Autodesk Fusion 360 part; units mm, degrees
(part 5 of 7)
equation "d301 = -( wall + 0.2 mm )"
equation "d303 = abs(( 1 ) * ( ( ( 1 ) * jointNodeQ * sqrt(2) - bodyWidth / 2 * cos(315 deg) + ( ( 1 ) * nodeHalfWidth ) * sin(315 deg) ) + ( 0 ) * ( ( 1 ) * endNodeX - ( ( 1 ) * jointNodeQ * sqrt(2) - bodyWidth / 2 * cos(315 deg) + ( ( 1 ) * nodeHalfWidth ) * sin(315 deg) ) ) ) + ( 0 ) * ( ( 1 ) * nodeHalfWidth ))"
equation "d304 = abs(( 0 ) * ( ( ( 1 ) * jointNodeQ * sqrt(2) - bodyWidth / 2 * cos(315 deg) + ( ( 1 ) * nodeHalfWidth ) * sin(315 deg) ) + ( 0 ) * ( ( 1 ) * endNodeX - ( ( 1 ) * jointNodeQ * sqrt(2) - bodyWidth / 2 * cos(315 deg) + ( ( 1 ) * nodeHalfWidth ) * sin(315 deg) ) ) ) + ( -1 ) * ( ( 1 ) * nodeHalfWidth ))"
equation "d305 = abs(( 1 ) * ( ( ( 1 ) * jointNodeQ * sqrt(2) - bodyWidth / 2 * cos(315 deg) + ( ( -1 ) * nodeHalfWidth ) * sin(315 deg) ) + ( 0.333333333333333 ) * ( ( 1 ) * endNodeX - ( ( 1 ) * jointNodeQ * sqrt(2) - bodyWidth / 2 * cos(315 deg) + ( ( -1 ) * nodeHalfWidth ) * sin(315 deg) ) ) ) + ( 0 ) * ( ( -1 ) * nodeHalfWidth ))"
equation "d306 = abs(( 0 ) * ( ( ( 1 ) * jointNodeQ * sqrt(2) - bodyWidth / 2 * cos(315 deg) + ( ( -1 ) * nodeHalfWidth ) * sin(315 deg) ) + ( 0.333333333333333 ) * ( ( 1 ) * endNodeX - ( ( 1 ) * jointNodeQ * sqrt(2) - bodyWidth / 2 * cos(315 deg) + ( ( -1 ) * nodeHalfWidth ) * sin(315 deg) ) ) ) + ( -1 ) * ( ( -1 ) * nodeHalfWidth ))"
equation "d307 = abs(( 1 ) * ( ( ( 1 ) * jointNodeQ * sqrt(2) - bodyWidth / 2 * cos(315 deg) + ( ( 1 ) * nodeHalfWidth ) * sin(315 deg) ) + ( 0.666666666666667 ) * ( ( 1 ) * endNodeX - ( ( 1 ) * jointNodeQ * sqrt(2) - bodyWidth / 2 * cos(315 deg) + ( ( 1 ) * nodeHalfWidth ) * sin(315 deg) ) ) ) + ( 0 ) * ( ( 1 ) * nodeHalfWidth ))"
equation "d308 = abs(( 0 ) * ( ( ( 1 ) * jointNodeQ * sqrt(2) - bodyWidth / 2 * cos(315 deg) + ( ( 1 ) * nodeHalfWidth ) * sin(315 deg) ) + ( 0.666666666666667 ) * ( ( 1 ) * endNodeX - ( ( 1 ) * jointNodeQ * sqrt(2) - bodyWidth / 2 * cos(315 deg) + ( ( 1 ) * nodeHalfWidth ) * sin(315 deg) ) ) ) + ( -1 ) * ( ( 1 ) * nodeHalfWidth ))"
equation "d309 = memberWidth / 2"
equation "d310 = -( wall + 0.2 mm )"
equation "d312 = abs(( 1 ) * ( ( ( 1 ) * jointNodeQ * sqrt(2) - bodyWidth / 2 * cos(315 deg) + ( ( -1 ) * nodeHalfWidth ) * sin(315 deg) ) + ( 0.333333333333333 ) * ( ( 1 ) * endNodeX - ( ( 1 ) * jointNodeQ * sqrt(2) - bodyWidth / 2 * cos(315 deg) + ( ( -1 ) * nodeHalfWidth ) * sin(315 deg) ) ) ) + ( 0 ) * ( ( -1 ) * nodeHalfWidth ))"
equation "d313 = abs(( 0 ) * ( ( ( 1 ) * jointNodeQ * sqrt(2) - bodyWidth / 2 * cos(315 deg) + ( ( -1 ) * nodeHalfWidth ) * sin(315 deg) ) + ( 0.333333333333333 ) * ( ( 1 ) * endNodeX - ( ( 1 ) * jointNodeQ * sqrt(2) - bodyWidth / 2 * cos(315 deg) + ( ( -1 ) * nodeHalfWidth ) * sin(315 deg) ) ) ) + ( -1 ) * ( ( -1 ) * nodeHalfWidth ))"
equation "d314 = abs(( 1 ) * ( ( ( 1 ) * jointNodeQ * sqrt(2) - bodyWidth / 2 * cos(315 deg) + ( ( 1 ) * nodeHalfWidth ) * sin(315 deg) ) + ( 0.666666666666667 ) * ( ( 1 ) * endNodeX - ( ( 1 ) * jointNodeQ * sqrt(2) - bodyWidth / 2 * cos(315 deg) + ( ( 1 ) * nodeHalfWidth ) * sin(315 deg) ) ) ) + ( 0 ) * ( ( 1 ) * nodeHalfWidth ))"
equation "d315 = abs(( 0 ) * ( ( ( 1 ) * jointNodeQ * sqrt(2) - bodyWidth / 2 * cos(315 deg) + ( ( 1 ) * nodeHalfWidth ) * sin(315 deg) ) + ( 0.666666666666667 ) * ( ( 1 ) * endNodeX - ( ( 1 ) * jointNodeQ * sqrt(2) - bodyWidth / 2 * cos(315 deg) + ( ( 1 ) * nodeHalfWidth ) * sin(315 deg) ) ) ) + ( -1 ) * ( ( 1 ) * nodeHalfWidth ))"
equation "d316 = abs(( 1 ) * ( ( ( 1 ) * jointNodeQ * sqrt(2) - bodyWidth / 2 * cos(315 deg) + ( ( -1 ) * nodeHalfWidth ) * sin(315 deg) ) + ( 1 ) * ( ( 1 ) * endNodeX - ( ( 1 ) * jointNodeQ * sqrt(2) - bodyWidth / 2 * cos(315 deg) + ( ( -1 ) * nodeHalfWidth ) * sin(315 deg) ) ) ) + ( 0 ) * ( ( -1 ) * nodeHalfWidth ))"
equation "d317 = abs(( 0 ) * ( ( ( 1 ) * jointNodeQ * sqrt(2) - bodyWidth / 2 * cos(315 deg) + ( ( -1 ) * nodeHalfWidth ) * sin(315 deg) ) + ( 1 ) * ( ( 1 ) * endNodeX - ( ( 1 ) * jointNodeQ * sqrt(2) - bodyWidth / 2 * cos(315 deg) + ( ( -1 ) * nodeHalfWidth ) * sin(315 deg) ) ) ) + ( -1 ) * ( ( -1 ) * nodeHalfWidth ))"
equation "d318 = -memberWidth / 2"
equation "d319 = -( wall + 0.2 mm )"
equation "d321 = abs(( 1 ) * ( ( ( 1 ) * jointNodeQ * sqrt(2) - bodyWidth / 2 * cos(315 deg) + ( ( 1 ) * nodeHalfWidth ) * sin(315 deg) ) + ( 0.666666666666667 ) * ( ( 1 ) * endNodeX - ( ( 1 ) * jointNodeQ * sqrt(2) - bodyWidth / 2 * cos(315 deg) + ( ( 1 ) * nodeHalfWidth ) * sin(315 deg) ) ) ) + ( 0 ) * ( ( 1 ) * nodeHalfWidth ))"
equation "d322 = abs(( 0 ) * ( ( ( 1 ) * jointNodeQ * sqrt(2) - bodyWidth / 2 * cos(315 deg) + ( ( 1 ) * nodeHalfWidth ) * sin(315 deg) ) + ( 0.666666666666667 ) * ( ( 1 ) * endNodeX - ( ( 1 ) * jointNodeQ * sqrt(2) - bodyWidth / 2 * cos(315 deg) + ( ( 1 ) * nodeHalfWidth ) * sin(315 deg) ) ) ) + ( -1 ) * ( ( 1 ) * nodeHalfWidth ))"
equation "d323 = abs(( 1 ) * ( ( ( 1 ) * jointNodeQ * sqrt(2) - bodyWidth / 2 * cos(315 deg) + ( ( -1 ) * nodeHalfWidth ) * sin(315 deg) ) + ( 1 ) * ( ( 1 ) * endNodeX - ( ( 1 ) * jointNodeQ * sqrt(2) - bodyWidth / 2 * cos(315 deg) + ( ( -1 ) * nodeHalfWidth ) * sin(315 deg) ) ) ) + ( 0 ) * ( ( -1 ) * nodeHalfWidth ))"
equation "d324 = abs(( 0 ) * ( ( ( 1 ) * jointNodeQ * sqrt(2) - bodyWidth / 2 * cos(315 deg) + ( ( -1 ) * nodeHalfWidth ) * sin(315 deg) ) + ( 1 ) * ( ( 1 ) * endNodeX - ( ( 1 ) * jointNodeQ * sqrt(2) - bodyWidth / 2 * cos(315 deg) + ( ( -1 ) * nodeHalfWidth ) * sin(315 deg) ) ) ) + ( -1 ) * ( ( -1 ) * nodeHalfWidth ))"
equation "d325 = abs(( 1 ) * ( ( ( 1 ) * jointNodeQ * sqrt(2) - bodyWidth / 2 * cos(315 deg) + ( ( 1 ) * nodeHalfWidth ) * sin(315 deg) ) + ( 1 ) * ( ( 1 ) * endNodeX - ( ( 1 ) * jointNodeQ * sqrt(2) - bodyWidth / 2 * cos(315 deg) + ( ( 1 ) * nodeHalfWidth ) * sin(315 deg) ) ) ) + ( 0 ) * ( ( 1 ) * nodeHalfWidth ))"
equation "d326 = abs(( 0 ) * ( ( ( 1 ) * jointNodeQ * sqrt(2) - bodyWidth / 2 * cos(315 deg) + ( ( 1 ) * nodeHalfWidth ) * sin(315 deg) ) + ( 1 ) * ( ( 1 ) * endNodeX - ( ( 1 ) * jointNodeQ * sqrt(2) - bodyWidth / 2 * cos(315 deg) + ( ( 1 ) * nodeHalfWidth ) * sin(315 deg) ) ) ) + ( -1 ) * ( ( 1 ) * nodeHalfWidth ))"
equation "d327 = memberWidth / 2"
equation "d328 = -( wall + 0.2 mm )"
equation "d331 = apertureRadius"
equation "d334 = bodyWidth / 2"
equation "d336 = abs(( 1 ) * ( ( ( -1 ) * jointNodeQ * sqrt(2) - bodyWidth / 2 * cos(0 deg) + ( ( -1 ) * nodeHalfWidth ) * sin(0 deg) ) + ( 0 ) * ( ( -1 ) * endNodeX - ( ( -1 ) * jointNodeQ * sqrt(2) - bodyWidth / 2 * cos(0 deg) + ( ( -1 ) * nodeHalfWidth ) * sin(0 deg) ) ) ) + ( 0 ) * ( ( -1 ) * nodeHalfWidth ))"
equation "d337 = abs(( 0 ) * ( ( ( -1 ) * jointNodeQ * sqrt(2) - bodyWidth / 2 * cos(0 deg) + ( ( -1 ) * nodeHalfWidth ) * sin(0 deg) ) + ( 0 ) * ( ( -1 ) * endNodeX - ( ( -1 ) * jointNodeQ * sqrt(2) - bodyWidth / 2 * cos(0 deg) + ( ( -1 ) * nodeHalfWidth ) * sin(0 deg) ) ) ) + ( -1 ) * ( ( -1 ) * nodeHalfWidth ))"
equation "d338 = abs(( 1 ) * ( ( ( -1 ) * jointNodeQ * sqrt(2) - bodyWidth / 2 * cos(0 deg) + ( ( 1 ) * nodeHalfWidth ) * sin(0 deg) ) + ( 0 ) * ( ( -1 ) * endNodeX - ( ( -1 ) * jointNodeQ * sqrt(2) - bodyWidth / 2 * cos(0 deg) + ( ( 1 ) * nodeHalfWidth ) * sin(0 deg) ) ) ) + ( 0 ) * ( ( 1 ) * nodeHalfWidth ))"
equation "d339 = abs(( 0 ) * ( ( ( -1 ) * jointNodeQ * sqrt(2) - bodyWidth / 2 * cos(0 deg) + ( ( 1 ) * nodeHalfWidth ) * sin(0 deg) ) + ( 0 ) * ( ( -1 ) * endNodeX - ( ( -1 ) * jointNodeQ * sqrt(2) - bodyWidth / 2 * cos(0 deg) + ( ( 1 ) * nodeHalfWidth ) * sin(0 deg) ) ) ) + ( -1 ) * ( ( 1 ) * nodeHalfWidth ))"
equation "d340 = abs(( 1 ) * ( ( ( -1 ) * jointNodeQ * sqrt(2) - bodyWidth / 2 * cos(0 deg) + ( ( -1 ) * nodeHalfWidth ) * sin(0 deg) ) + ( 1 ) * ( ( -1 ) * endNodeX - ( ( -1 ) * jointNodeQ * sqrt(2) - bodyWidth / 2 * cos(0 deg) + ( ( -1 ) * nodeHalfWidth ) * sin(0 deg) ) ) ) + ( 0 ) * ( ( -1 ) * nodeHalfWidth ))"
equation "d341 = abs(( 0 ) * ( ( ( -1 ) * jointNodeQ * sqrt(2) - bodyWidth / 2 * cos(0 deg) + ( ( -1 ) * nodeHalfWidth ) * sin(0 deg) ) + ( 1 ) * ( ( -1 ) * endNodeX - ( ( -1 ) * jointNodeQ * sqrt(2) - bodyWidth / 2 * cos(0 deg) + ( ( -1 ) * nodeHalfWidth ) * sin(0 deg) ) ) ) + ( -1 ) * ( ( -1 ) * nodeHalfWidth ))"
equation "d342 = memberWidth / 2"
equation "d343 = -( wall + 0.2 mm )"
equation "d345 = abs(( 1 ) * ( ( ( -1 ) * jointNodeQ * sqrt(2) - bodyWidth / 2 * cos(0 deg) + ( ( 1 ) * nodeHalfWidth ) * sin(0 deg) ) + ( 0 ) * ( ( -1 ) * endNodeX - ( ( -1 ) * jointNodeQ * sqrt(2) - bodyWidth / 2 * cos(0 deg) + ( ( 1 ) * nodeHalfWidth ) * sin(0 deg) ) ) ) + ( 0 ) * ( ( 1 ) * nodeHalfWidth ))"
equation "d346 = abs(( 0 ) * ( ( ( -1 ) * jointNodeQ * sqrt(2) - bodyWidth / 2 * cos(0 deg) + ( ( 1 ) * nodeHalfWidth ) * sin(0 deg) ) + ( 0 ) * ( ( -1 ) * endNodeX - ( ( -1 ) * jointNodeQ * sqrt(2) - bodyWidth / 2 * cos(0 deg) + ( ( 1 ) * nodeHalfWidth ) * sin(0 deg) ) ) ) + ( -1 ) * ( ( 1 ) * nodeHalfWidth ))"
equation "d347 = abs(( 1 ) * ( ( ( -1 ) * jointNodeQ * sqrt(2) - bodyWidth / 2 * cos(0 deg) + ( ( -1 ) * nodeHalfWidth ) * sin(0 deg) ) + ( 1 ) * ( ( -1 ) * endNodeX - ( ( -1 ) * jointNodeQ * sqrt(2) - bodyWidth / 2 * cos(0 deg) + ( ( -1 ) * nodeHalfWidth ) * sin(0 deg) ) ) ) + ( 0 ) * ( ( -1 ) * nodeHalfWidth ))"
equation "d348 = abs(( 0 ) * ( ( ( -1 ) * jointNodeQ * sqrt(2) - bodyWidth / 2 * cos(0 deg) + ( ( -1 ) * nodeHalfWidth ) * sin(0 deg) ) + ( 1 ) * ( ( -1 ) * endNodeX - ( ( -1 ) * jointNodeQ * sqrt(2) - bodyWidth / 2 * cos(0 deg) + ( ( -1 ) * nodeHalfWidth ) * sin(0 deg) ) ) ) + ( -1 ) * ( ( -1 ) * nodeHalfWidth ))"
equation "d349 = abs(( 1 ) * ( ( ( -1 ) * jointNodeQ * sqrt(2) - bodyWidth / 2 * cos(0 deg) + ( ( 1 ) * nodeHalfWidth ) * sin(0 deg) ) + ( 1 ) * ( ( -1 ) * endNodeX - ( ( -1 ) * jointNodeQ * sqrt(2) - bodyWidth / 2 * cos(0 deg) + ( ( 1 ) * nodeHalfWidth ) * sin(0 deg) ) ) ) + ( 0 ) * ( ( 1 ) * nodeHalfWidth ))"
equation "d350 = abs(( 0 ) * ( ( ( -1 ) * jointNodeQ * sqrt(2) - bodyWidth / 2 * cos(0 deg) + ( ( 1 ) * nodeHalfWidth ) * sin(0 deg) ) + ( 1 ) * ( ( -1 ) * endNodeX - ( ( -1 ) * jointNodeQ * sqrt(2) - bodyWidth / 2 * cos(0 deg) + ( ( 1 ) * nodeHalfWidth ) * sin(0 deg) ) ) ) + ( -1 ) * ( ( 1 ) * nodeHalfWidth ))"
equation "d351 = -memberWidth / 2"
equation "d352 = -( wall + 0.2 mm )"
equation "d355 = apertureRadius"
equation "d358 = bodyWidth / 2"
equation "d360 = abs(( 1 ) * ( ( ( -1 ) * jointNodeQ * sqrt(2) - bodyWidth / 2 * cos(45 deg) + ( ( -1 ) * nodeHalfWidth ) * sin(45 deg) ) + ( 0 ) * ( ( -1 ) * endNodeX - ( ( -1 ) * jointNodeQ * sqrt(2) - bodyWidth / 2 * cos(45 deg) + ( ( -1 ) * nodeHalfWidth ) * sin(45 deg) ) ) ) + ( 0 ) * ( ( -1 ) * nodeHalfWidth ))"
equation "d361 = abs(( 0 ) * ( ( ( -1 ) * jointNodeQ * sqrt(2) - bodyWidth / 2 * cos(45 deg) + ( ( -1 ) * nodeHalfWidth ) * sin(45 deg) ) + ( 0 ) * ( ( -1 ) * endNodeX - ( ( -1 ) * jointNodeQ * sqrt(2) - bodyWidth / 2 * cos(45 deg) + ( ( -1 ) * nodeHalfWidth ) * sin(45 deg) ) ) ) + ( -1 ) * ( ( -1 ) * nodeHalfWidth ))"
equation "d362 = abs(( 1 ) * ( ( ( -1 ) * jointNodeQ * sqrt(2) - bodyWidth / 2 * cos(45 deg) + ( ( 1 ) * nodeHalfWidth ) * sin(45 deg) ) + ( 0 ) * ( ( -1 ) * endNodeX - ( ( -1 ) * jointNodeQ * sqrt(2) - bodyWidth / 2 * cos(45 deg) + ( ( 1 ) * nodeHalfWidth ) * sin(45 deg) ) ) ) + ( 0 ) * ( ( 1 ) * nodeHalfWidth ))"
equation "d363 = abs(( 0 ) * ( ( ( -1 ) * jointNodeQ * sqrt(2) - bodyWidth / 2 * cos(45 deg) + ( ( 1 ) * nodeHalfWidth ) * sin(45 deg) ) + ( 0 ) * ( ( -1 ) * endNodeX - ( ( -1 ) * jointNodeQ * sqrt(2) - bodyWidth / 2 * cos(45 deg) + ( ( 1 ) * nodeHalfWidth ) * sin(45 deg) ) ) ) + ( -1 ) * ( ( 1 ) * nodeHalfWidth ))"
equation "d364 = abs(( 1 ) * ( ( ( -1 ) * jointNodeQ * sqrt(2) - bodyWidth / 2 * cos(45 deg) + ( ( -1 ) * nodeHalfWidth ) * sin(45 deg) ) + ( 1 ) * ( ( -1 ) * endNodeX - ( ( -1 ) * jointNodeQ * sqrt(2) - bodyWidth / 2 * cos(45 deg) + ( ( -1 ) * nodeHalfWidth ) * sin(45 deg) ) ) ) + ( 0 ) * ( ( -1 ) * nodeHalfWidth ))"
equation "d365 = abs(( 0 ) * ( ( ( -1 ) * jointNodeQ * sqrt(2) - bodyWidth / 2 * cos(45 deg) + ( ( -1 ) * nodeHalfWidth ) * sin(45 deg) ) + ( 1 ) * ( ( -1 ) * endNodeX - ( ( -1 ) * jointNodeQ * sqrt(2) - bodyWidth / 2 * cos(45 deg) + ( ( -1 ) * nodeHalfWidth ) * sin(45 deg) ) ) ) + ( -1 ) * ( ( -1 ) * nodeHalfWidth ))"
equation "d366 = memberWidth / 2"
equation "d367 = -( wall + 0.2 mm )"
equation "d369 = abs(( 1 ) * ( ( ( -1 ) * jointNodeQ * sqrt(2) - bodyWidth / 2 * cos(45 deg) + ( ( 1 ) * nodeHalfWidth ) * sin(45 deg) ) + ( 0 ) * ( ( -1 ) * endNodeX - ( ( -1 ) * jointNodeQ * sqrt(2) - bodyWidth / 2 * cos(45 deg) + ( ( 1 ) * nodeHalfWidth ) * sin(45 deg) ) ) ) + ( 0 ) * ( ( 1 ) * nodeHalfWidth ))"
equation "d370 = abs(( 0 ) * ( ( ( -1 ) * jointNodeQ * sqrt(2) - bodyWidth / 2 * cos(45 deg) + ( ( 1 ) * nodeHalfWidth ) * sin(45 deg) ) + ( 0 ) * ( ( -1 ) * endNodeX - ( ( -1 ) * jointNodeQ * sqrt(2) - bodyWidth / 2 * cos(45 deg) + ( ( 1 ) * nodeHalfWidth ) * sin(45 deg) ) ) ) + ( -1 ) * ( ( 1 ) * nodeHalfWidth ))"
equation "d371 = abs(( 1 ) * ( ( ( -1 ) * jointNodeQ * sqrt(2) - bodyWidth / 2 * cos(45 deg) + ( ( -1 ) * nodeHalfWidth ) * sin(45 deg) ) + ( 1 ) * ( ( -1 ) * endNodeX - ( ( -1 ) * jointNodeQ * sqrt(2) - bodyWidth / 2 * cos(45 deg) + ( ( -1 ) * nodeHalfWidth ) * sin(45 deg) ) ) ) + ( 0 ) * ( ( -1 ) * nodeHalfWidth ))"
equation "d372 = abs(( 0 ) * ( ( ( -1 ) * jointNodeQ * sqrt(2) - bodyWidth / 2 * cos(45 deg) + ( ( -1 ) * nodeHalfWidth ) * sin(45 deg) ) + ( 1 ) * ( ( -1 ) * endNodeX - ( ( -1 ) * jointNodeQ * sqrt(2) - bodyWidth / 2 * cos(45 deg) + ( ( -1 ) * nodeHalfWidth ) * sin(45 deg) ) ) ) + ( -1 ) * ( ( -1 ) * nodeHalfWidth ))"
equation "d373 = abs(( 1 ) * ( ( ( -1 ) * jointNodeQ * sqrt(2) - bodyWidth / 2 * cos(45 deg) + ( ( 1 ) * nodeHalfWidth ) * sin(45 deg) ) + ( 1 ) * ( ( -1 ) * endNodeX - ( ( -1 ) * jointNodeQ * sqrt(2) - bodyWidth / 2 * cos(45 deg) + ( ( 1 ) * nodeHalfWidth ) * sin(45 deg) ) ) ) + ( 0 ) * ( ( 1 ) * nodeHalfWidth ))"
equation "d374 = abs(( 0 ) * ( ( ( -1 ) * jointNodeQ * sqrt(2) - bodyWidth / 2 * cos(45 deg) + ( ( 1 ) * nodeHalfWidth ) * sin(45 deg) ) + ( 1 ) * ( ( -1 ) * endNodeX - ( ( -1 ) * jointNodeQ * sqrt(2) - bodyWidth / 2 * cos(45 deg) + ( ( 1 ) * nodeHalfWidth ) * sin(45 deg) ) ) ) + ( -1 ) * ( ( 1 ) * nodeHalfWidth ))"
equation "d375 = -memberWidth / 2"
equation "d376 = -( wall + 0.2 mm )"
equation "d379 = apertureRadius"
equation "d382 = bodyWidth / 2"
equation "d384 = abs(( 1 ) * ( ( ( -1 ) * jointNodeQ * sqrt(2) - bodyWidth / 2 * cos(90 deg) + ( ( 1 ) * nodeHalfWidth ) * sin(90 deg) ) + ( 0 ) * ( ( -1 ) * endNodeX - ( ( -1 ) * jointNodeQ * sqrt(2) - bodyWidth / 2 * cos(90 deg) + ( ( 1 ) * nodeHalfWidth ) * sin(90 deg) ) ) ) + ( 0 ) * ( ( 1 ) * nodeHalfWidth ))"
equation "d385 = abs(( 0 ) * ( ( ( -1 ) * jointNodeQ * sqrt(2) - bodyWidth / 2 * cos(90 deg) + ( ( 1 ) * nodeHalfWidth ) * sin(90 deg) ) + ( 0 ) * ( ( -1 ) * endNodeX - ( ( -1 ) * jointNodeQ * sqrt(2) - bodyWidth / 2 * cos(90 deg) + ( ( 1 ) * nodeHalfWidth ) * sin(90 deg) ) ) ) + ( -1 ) * ( ( 1 ) * nodeHalfWidth ))"
equation "d386 = abs(( 1 ) * ( ( ( -1 ) * jointNodeQ * sqrt(2) - bodyWidth / 2 * cos(90 deg) + ( ( -1 ) * nodeHalfWidth ) * sin(90 deg) ) + ( 0 ) * ( ( -1 ) * endNodeX - ( ( -1 ) * jointNodeQ * sqrt(2) - bodyWidth / 2 * cos(90 deg) + ( ( -1 ) * nodeHalfWidth ) * sin(90 deg) ) ) ) + ( 0 ) * ( ( -1 ) * nodeHalfWidth ))"
equation "d387 = abs(( 0 ) * ( ( ( -1 ) * jointNodeQ * sqrt(2) - bodyWidth / 2 * cos(90 deg) + ( ( -1 ) * nodeHalfWidth ) * sin(90 deg) ) + ( 0 ) * ( ( -1 ) * endNodeX - ( ( -1 ) * jointNodeQ * sqrt(2) - bodyWidth / 2 * cos(90 deg) + ( ( -1 ) * nodeHalfWidth ) * sin(90 deg) ) ) ) + ( -1 ) * ( ( -1 ) * nodeHalfWidth ))"
equation "d388 = abs(( 1 ) * ( ( ( -1 ) * jointNodeQ * sqrt(2) - bodyWidth / 2 * cos(90 deg) + ( ( 1 ) * nodeHalfWidth ) * sin(90 deg) ) + ( 0.5 ) * ( ( -1 ) * endNodeX - ( ( -1 ) * jointNodeQ * sqrt(2) - bodyWidth / 2 * cos(90 deg) + ( ( 1 ) * nodeHalfWidth ) * sin(90 deg) ) ) ) + ( 0 ) * ( ( 1 ) * nodeHalfWidth ))"
equation "d389 = abs(( 0 ) * ( ( ( -1 ) * jointNodeQ * sqrt(2) - bodyWidth / 2 * cos(90 deg) + ( ( 1 ) * nodeHalfWidth ) * sin(90 deg) ) + ( 0.5 ) * ( ( -1 ) * endNodeX - ( ( -1 ) * jointNodeQ * sqrt(2) - bodyWidth / 2 * cos(90 deg) + ( ( 1 ) * nodeHalfWidth ) * sin(90 deg) ) ) ) + ( -1 ) * ( ( 1 ) * nodeHalfWidth ))"
equation "d390 = -memberWidth / 2"
equation "d391 = -( wall + 0.2 mm )"
equation "d393 = abs(( 1 ) * ( ( ( -1 ) * jointNodeQ * sqrt(2) - bodyWidth / 2 * cos(90 deg) + ( ( -1 ) * nodeHalfWidth ) * sin(90 deg) ) + ( 0 ) * ( ( -1 ) * endNodeX - ( ( -1 ) * jointNodeQ * sqrt(2) - bodyWidth / 2 * cos(90 deg) + ( ( -1 ) * nodeHalfWidth ) * sin(90 deg) ) ) ) + ( 0 ) * ( ( -1 ) * nodeHalfWidth ))"
equation "d394 = abs(( 0 ) * ( ( ( -1 ) * jointNodeQ * sqrt(2) - bodyWidth / 2 * cos(90 deg) + ( ( -1 ) * nodeHalfWidth ) * sin(90 deg) ) + ( 0 ) * ( ( -1 ) * endNodeX - ( ( -1 ) * jointNodeQ * sqrt(2) - bodyWidth / 2 * cos(90 deg) + ( ( -1 ) * nodeHalfWidth ) * sin(90 deg) ) ) ) + ( -1 ) * ( ( -1 ) * nodeHalfWidth ))"
equation "d395 = abs(( 1 ) * ( ( ( -1 ) * jointNodeQ * sqrt(2) - bodyWidth / 2 * cos(90 deg) + ( ( 1 ) * nodeHalfWidth ) * sin(90 deg) ) + ( 0.5 ) * ( ( -1 ) * endNodeX - ( ( -1 ) * jointNodeQ * sqrt(2) - bodyWidth / 2 * cos(90 deg) + ( ( 1 ) * nodeHalfWidth ) * sin(90 deg) ) ) ) + ( 0 ) * ( ( 1 ) * nodeHalfWidth ))"
equation "d396 = abs(( 0 ) * ( ( ( -1 ) * jointNodeQ * sqrt(2) - bodyWidth / 2 * cos(90 deg) + ( ( 1 ) * nodeHalfWidth ) * sin(90 deg) ) + ( 0.5 ) * ( ( -1 ) * endNodeX - ( ( -1 ) * jointNodeQ * sqrt(2) - bodyWidth / 2 * cos(90 deg) + ( ( 1 ) * nodeHalfWidth ) * sin(90 deg) ) ) ) + ( -1 ) * ( ( 1 ) * nodeHalfWidth ))"
equation "d397 = abs(( 1 ) * ( ( ( -1 ) * jointNodeQ * sqrt(2) - bodyWidth / 2 * cos(90 deg) + ( ( -1 ) * nodeHalfWidth ) * sin(90 deg) ) + ( 1 ) * ( ( -1 ) * endNodeX - ( ( -1 ) * jointNodeQ * sqrt(2) - bodyWidth / 2 * cos(90 deg) + ( ( -1 ) * nodeHalfWidth ) * sin(90 deg) ) ) ) + ( 0 ) * ( ( -1 ) * nodeHalfWidth ))"
equation "d398 = abs(( 0 ) * ( ( ( -1 ) * jointNodeQ * sqrt(2) - bodyWidth / 2 * cos(90 deg) + ( ( -1 ) * nodeHalfWidth ) * sin(90 deg) ) + ( 1 ) * ( ( -1 ) * endNodeX - ( ( -1 ) * jointNodeQ * sqrt(2) - bodyWidth / 2 * cos(90 deg) + ( ( -1 ) * nodeHalfWidth ) * sin(90 deg) ) ) ) + ( -1 ) * ( ( -1 ) * nodeHalfWidth ))"
equation "d399 = memberWidth / 2"
equation "d400 = -( wall + 0.2 mm )"
equation "d402 = abs(( 1 ) * ( ( ( -1 ) * jointNodeQ * sqrt(2) - bodyWidth / 2 * cos(90 deg) + ( ( 1 ) * nodeHalfWidth ) * sin(90 deg) ) + ( 0.5 ) * ( ( -1 ) * endNodeX - ( ( -1 ) * jointNodeQ * sqrt(2) - bodyWidth / 2 * cos(90 deg) + ( ( 1 ) * nodeHalfWidth ) * sin(90 deg) ) ) ) + ( 0 ) * ( ( 1 ) * nodeHalfWidth ))"
equation "d403 = abs(( 0 ) * ( ( ( -1 ) * jointNodeQ * sqrt(2) - bodyWidth / 2 * cos(90 deg) + ( ( 1 ) * nodeHalfWidth ) * sin(90 deg) ) + ( 0.5 ) * ( ( -1 ) * endNodeX - ( ( -1 ) * jointNodeQ * sqrt(2) - bodyWidth / 2 * cos(90 deg) + ( ( 1 ) * nodeHalfWidth ) * sin(90 deg) ) ) ) + ( -1 ) * ( ( 1 ) * nodeHalfWidth ))"
equation "d404 = abs(( 1 ) * ( ( ( -1 ) * jointNodeQ * sqrt(2) - bodyWidth / 2 * cos(90 deg) + ( ( -1 ) * nodeHalfWidth ) * sin(90 deg) ) + ( 1 ) * ( ( -1 ) * endNodeX - ( ( -1 ) * jointNodeQ * sqrt(2) - bodyWidth / 2 * cos(90 deg) + ( ( -1 ) * nodeHalfWidth ) * sin(90 deg) ) ) ) + ( 0 ) * ( ( -1 ) * nodeHalfWidth ))"
equation "d405 = abs(( 0 ) * ( ( ( -1 ) * jointNodeQ * sqrt(2) - bodyWidth / 2 * cos(90 deg) + ( ( -1 ) * nodeHalfWidth ) * sin(90 deg) ) + ( 1 ) * ( ( -1 ) * endNodeX - ( ( -1 ) * jointNodeQ * sqrt(2) - bodyWidth / 2 * cos(90 deg) + ( ( -1 ) * nodeHalfWidth ) * sin(90 deg) ) ) ) + ( -1 ) * ( ( -1 ) * nodeHalfWidth ))"
equation "d406 = abs(( 1 ) * ( ( ( -1 ) * jointNodeQ * sqrt(2) - bodyWidth / 2 * cos(90 deg) + ( ( 1 ) * nodeHalfWidth ) * sin(90 deg) ) + ( 1 ) * ( ( -1 ) * endNodeX - ( ( -1 ) * jointNodeQ * sqrt(2) - bodyWidth / 2 * cos(90 deg) + ( ( 1 ) * nodeHalfWidth ) * sin(90 deg) ) ) ) + ( 0 ) * ( ( 1 ) * nodeHalfWidth ))"
equation "d407 = abs(( 0 ) * ( ( ( -1 ) * jointNodeQ * sqrt(2) - bodyWidth / 2 * cos(90 deg) + ( ( 1 ) * nodeHalfWidth ) * sin(90 deg) ) + ( 1 ) * ( ( -1 ) * endNodeX - ( ( -1 ) * jointNodeQ * sqrt(2) - bodyWidth / 2 * cos(90 deg) + ( ( 1 ) * nodeHalfWidth ) * sin(90 deg) ) ) ) + ( -1 ) * ( ( 1 ) * nodeHalfWidth ))"
equation "d408 = -memberWidth / 2"
equation "d409 = -( wall + 0.2 mm )"
equation "d412 = apertureRadius"
equation "d415 = bodyWidth / 2"
equation "d417 = abs(( 1 ) * ( ( ( -1 ) * jointNodeQ * sqrt(2) - bodyWidth / 2 * cos(135 deg) + ( ( -1 ) * nodeHalfWidth ) * sin(135 deg) ) + ( 0 ) * ( ( -1 ) * endNodeX - ( ( -1 ) * jointNodeQ * sqrt(2) - bodyWidth / 2 * cos(135 deg) + ( ( -1 ) * nodeHalfWidth ) * sin(135 deg) ) ) ) + ( 0 ) * ( ( -1 ) * nodeHalfWidth ))"
equation "d418 = abs(( 0 ) * ( ( ( -1 ) * jointNodeQ * sqrt(2) - bodyWidth / 2 * cos(135 deg) + ( ( -1 ) * nodeHalfWidth ) * sin(135 deg) ) + ( 0 ) * ( ( -1 ) * endNodeX - ( ( -1 ) * jointNodeQ * sqrt(2) - bodyWidth / 2 * cos(135 deg) + ( ( -1 ) * nodeHalfWidth ) * sin(135 deg) ) ) ) + ( -1 ) * ( ( -1 ) * nodeHalfWidth ))"
equation "d419 = abs(( 1 ) * ( ( ( -1 ) * jointNodeQ * sqrt(2) - bodyWidth / 2 * cos(135 deg) + ( ( 1 ) * nodeHalfWidth ) * sin(135 deg) ) + ( 0 ) * ( ( -1 ) * endNodeX - ( ( -1 ) * jointNodeQ * sqrt(2) - bodyWidth / 2 * cos(135 deg) + ( ( 1 ) * nodeHalfWidth ) * sin(135 deg) ) ) ) + ( 0 ) * ( ( 1 ) * nodeHalfWidth ))"
equation "d420 = abs(( 0 ) * ( ( ( -1 ) * jointNodeQ * sqrt(2) - bodyWidth / 2 * cos(135 deg) + ( ( 1 ) * nodeHalfWidth ) * sin(135 deg) ) + ( 0 ) * ( ( -1 ) * endNodeX - ( ( -1 ) * jointNodeQ * sqrt(2) - bodyWidth / 2 * cos(135 deg) + ( ( 1 ) * nodeHalfWidth ) * sin(135 deg) ) ) ) + ( -1 ) * ( ( 1 ) * nodeHalfWidth ))"
equation "d421 = abs(( 1 ) * ( ( ( -1 ) * jointNodeQ * sqrt(2) - bodyWidth / 2 * cos(135 deg) + ( ( -1 ) * nodeHalfWidth ) * sin(135 deg) ) + ( 0.333333333333333 ) * ( ( -1 ) * endNodeX - ( ( -1 ) * jointNodeQ * sqrt(2) - bodyWidth / 2 * cos(135 deg) + ( ( -1 ) * nodeHalfWidth ) * sin(135 deg) ) ) ) + ( 0 ) * ( ( -1 ) * nodeHalfWidth ))"
equation "d422 = abs(( 0 ) * ( ( ( -1 ) * jointNodeQ * sqrt(2) - bodyWidth / 2 * cos(135 deg) + ( ( -1 ) * nodeHalfWidth ) * sin(135 deg) ) + ( 0.333333333333333 ) * ( ( -1 ) * endNodeX - ( ( -1 ) * jointNodeQ * sqrt(2) - bodyWidth / 2 * cos(135 deg) + ( ( -1 ) * nodeHalfWidth ) * sin(135 deg) ) ) ) + ( -1 ) * ( ( -1 ) * nodeHalfWidth ))"
equation "d423 = memberWidth / 2"
equation "d424 = -( wall + 0.2 mm )"
equation "d426 = abs(( 1 ) * ( ( ( -1 ) * jointNodeQ * sqrt(2) - bodyWidth / 2 * cos(135 deg) + ( ( 1 ) * nodeHalfWidth ) * sin(135 deg) ) + ( 0 ) * ( ( -1 ) * endNodeX - ( ( -1 ) * jointNodeQ * sqrt(2) - bodyWidth / 2 * cos(135 deg) + ( ( 1 ) * nodeHalfWidth ) * sin(135 deg) ) ) ) + ( 0 ) * ( ( 1 ) * nodeHalfWidth ))"
equation "d427 = abs(( 0 ) * ( ( ( -1 ) * jointNodeQ * sqrt(2) - bodyWidth / 2 * cos(135 deg) + ( ( 1 ) * nodeHalfWidth ) * sin(135 deg) ) + ( 0 ) * ( ( -1 ) * endNodeX - ( ( -1 ) * jointNodeQ * sqrt(2) - bodyWidth / 2 * cos(135 deg) + ( ( 1 ) * nodeHalfWidth ) * sin(135 deg) ) ) ) + ( -1 ) * ( ( 1 ) * nodeHalfWidth ))"
equation "d428 = abs(( 1 ) * ( ( ( -1 ) * jointNodeQ * sqrt(2) - bodyWidth / 2 * cos(135 deg) + ( ( -1 ) * nodeHalfWidth ) * sin(135 deg) ) + ( 0.333333333333333 ) * ( ( -1 ) * endNodeX - ( ( -1 ) * jointNodeQ * sqrt(2) - bodyWidth / 2 * cos(135 deg) + ( ( -1 ) * nodeHalfWidth ) * sin(135 deg) ) ) ) + ( 0 ) * ( ( -1 ) * nodeHalfWidth ))"
equation "d429 = abs(( 0 ) * ( ( ( -1 ) * jointNodeQ * sqrt(2) - bodyWidth / 2 * cos(135 deg) + ( ( -1 ) * nodeHalfWidth ) * sin(135 deg) ) + ( 0.333333333333333 ) * ( ( -1 ) * endNodeX - ( ( -1 ) * jointNodeQ * sqrt(2) - bodyWidth / 2 * cos(135 deg) + ( ( -1 ) * nodeHalfWidth ) * sin(135 deg) ) ) ) + ( -1 ) * ( ( -1 ) * nodeHalfWidth ))"
equation "d430 = abs(( 1 ) * ( ( ( -1 ) * jointNodeQ * sqrt(2) - bodyWidth / 2 * cos(135 deg) + ( ( 1 ) * nodeHalfWidth ) * sin(135 deg) ) + ( 0.666666666666667 ) * ( ( -1 ) * endNodeX - ( ( -1 ) * jointNodeQ * sqrt(2) - bodyWidth / 2 * cos(135 deg) + ( ( 1 ) * nodeHalfWidth ) * sin(135 deg) ) ) ) + ( 0 ) * ( ( 1 ) * nodeHalfWidth ))"
equation "d431 = abs(( 0 ) * ( ( ( -1 ) * jointNodeQ * sqrt(2) - bodyWidth / 2 * cos(135 deg) + ( ( 1 ) * nodeHalfWidth ) * sin(135 deg) ) + ( 0.666666666666667 ) * ( ( -1 ) * endNodeX - ( ( -1 ) * jointNodeQ * sqrt(2) - bodyWidth / 2 * cos(135 deg) + ( ( 1 ) * nodeHalfWidth ) * sin(135 deg) ) ) ) + ( -1 ) * ( ( 1 ) * nodeHalfWidth ))"
equation "d432 = -memberWidth / 2"
equation "d433 = -( wall + 0.2 mm )"
equation "d435 = abs(( 1 ) * ( ( ( -1 ) * jointNodeQ * sqrt(2) - bodyWidth / 2 * cos(135 deg) + ( ( -1 ) * nodeHalfWidth ) * sin(135 deg) ) + ( 0.333333333333333 ) * ( ( -1 ) * endNodeX - ( ( -1 ) * jointNodeQ * sqrt(2) - bodyWidth / 2 * cos(135 deg) + ( ( -1 ) * nodeHalfWidth ) * sin(135 deg) ) ) ) + ( 0 ) * ( ( -1 ) * nodeHalfWidth ))"
equation "d436 = abs(( 0 ) * ( ( ( -1 ) * jointNodeQ * sqrt(2) - bodyWidth / 2 * cos(135 deg) + ( ( -1 ) * nodeHalfWidth ) * sin(135 deg) ) + ( 0.333333333333333 ) * ( ( -1 ) * endNodeX - ( ( -1 ) * jointNodeQ * sqrt(2) - bodyWidth / 2 * cos(135 deg) + ( ( -1 ) * nodeHalfWidth ) * sin(135 deg) ) ) ) + ( -1 ) * ( ( -1 ) * nodeHalfWidth ))"
equation "d437 = abs(( 1 ) * ( ( ( -1 ) * jointNodeQ * sqrt(2) - bodyWidth / 2 * cos(135 deg) + ( ( 1 ) * nodeHalfWidth ) * sin(135 deg) ) + ( 0.666666666666667 ) * ( ( -1 ) * endNodeX - ( ( -1 ) * jointNodeQ * sqrt(2) - bodyWidth / 2 * cos(135 deg) + ( ( 1 ) * nodeHalfWidth ) * sin(135 deg) ) ) ) + ( 0 ) * ( ( 1 ) * nodeHalfWidth ))"
equation "d438 = abs(( 0 ) * ( ( ( -1 ) * jointNodeQ * sqrt(2) - bodyWidth / 2 * cos(135 deg) + ( ( 1 ) * nodeHalfWidth ) * sin(135 deg) ) + ( 0.666666666666667 ) * ( ( -1 ) * endNodeX - ( ( -1 ) * jointNodeQ * sqrt(2) - bodyWidth / 2 * cos(135 deg) + ( ( 1 ) * nodeHalfWidth ) * sin(135 deg) ) ) ) + ( -1 ) * ( ( 1 ) * nodeHalfWidth ))"
equation "d439 = abs(( 1 ) * ( ( ( -1 ) * jointNodeQ * sqrt(2) - bodyWidth / 2 * cos(135 deg) + ( ( -1 ) * nodeHalfWidth ) * sin(135 deg) ) + ( 1 ) * ( ( -1 ) * endNodeX - ( ( -1 ) * jointNodeQ * sqrt(2) - bodyWidth / 2 * cos(135 deg) + ( ( -1 ) * nodeHalfWidth ) * sin(135 deg) ) ) ) + ( 0 ) * ( ( -1 ) * nodeHalfWidth ))"
equation "d440 = abs(( 0 ) * ( ( ( -1 ) * jointNodeQ * sqrt(2) - bodyWidth / 2 * cos(135 deg) + ( ( -1 ) * nodeHalfWidth ) * sin(135 deg) ) + ( 1 ) * ( ( -1 ) * endNodeX - ( ( -1 ) * jointNodeQ * sqrt(2) - bodyWidth / 2 * cos(135 deg) + ( ( -1 ) * nodeHalfWidth ) * sin(135 deg) ) ) ) + ( -1 ) * ( ( -1 ) * nodeHalfWidth ))"
equation "d441 = memberWidth / 2"
equation "d442 = -( wall + 0.2 mm )"
equation "d444 = abs(( 1 ) * ( ( ( -1 ) * jointNodeQ * sqrt(2) - bodyWidth / 2 * cos(135 deg) + ( ( 1 ) * nodeHalfWidth ) * sin(135 deg) ) + ( 0.666666666666667 ) * ( ( -1 ) * endNodeX - ( ( -1 ) * jointNodeQ * sqrt(2) - bodyWidth / 2 * cos(135 deg) + ( ( 1 ) * nodeHalfWidth ) * sin(135 deg) ) ) ) + ( 0 ) * ( ( 1 ) * nodeHalfWidth ))"
equation "d445 = abs(( 0 ) * ( ( ( -1 ) * jointNodeQ * sqrt(2) - bodyWidth / 2 * cos(135 deg) + ( ( 1 ) * nodeHalfWidth ) * sin(135 deg) ) + ( 0.666666666666667 ) * ( ( -1 ) * endNodeX - ( ( -1 ) * jointNodeQ * sqrt(2) - bodyWidth / 2 * cos(135 deg) + ( ( 1 ) * nodeHalfWidth ) * sin(135 deg) ) ) ) + ( -1 ) * ( ( 1 ) * nodeHalfWidth ))"
equation "d446 = abs(( 1 ) * ( ( ( -1 ) * jointNodeQ * sqrt(2) - bodyWidth / 2 * cos(135 deg) + ( ( -1 ) * nodeHalfWidth ) * sin(135 deg) ) + ( 1 ) * ( ( -1 ) * endNodeX - ( ( -1 ) * jointNodeQ * sqrt(2) - bodyWidth / 2 * cos(135 deg) + ( ( -1 ) * nodeHalfWidth ) * sin(135 deg) ) ) ) + ( 0 ) * ( ( -1 ) * nodeHalfWidth ))"
equation "d447 = abs(( 0 ) * ( ( ( -1 ) * jointNodeQ * sqrt(2) - bodyWidth / 2 * cos(135 deg) + ( ( -1 ) * nodeHalfWidth ) * sin(135 deg) ) + ( 1 ) * ( ( -1 ) * endNodeX - ( ( -1 ) * jointNodeQ * sqrt(2) - bodyWidth / 2 * cos(135 deg) + ( ( -1 ) * nodeHalfWidth ) * sin(135 deg) ) ) ) + ( -1 ) * ( ( -1 ) * nodeHalfWidth ))"
equation "d448 = abs(( 1 ) * ( ( ( -1 ) * jointNodeQ * sqrt(2) - bodyWidth / 2 * cos(135 deg) + ( ( 1 ) * nodeHalfWidth ) * sin(135 deg) ) + ( 1 ) * ( ( -1 ) * endNodeX - ( ( -1 ) * jointNodeQ * sqrt(2) - bodyWidth / 2 * cos(135 deg) + ( ( 1 ) * nodeHalfWidth ) * sin(135 deg) ) ) ) + ( 0 ) * ( ( 1 ) * nodeHalfWidth ))"
equation "d449 = abs(( 0 ) * ( ( ( -1 ) * jointNodeQ * sqrt(2) - bodyWidth / 2 * cos(135 deg) + ( ( 1 ) * nodeHalfWidth ) * sin(135 deg) ) + ( 1 ) * ( ( -1 ) * endNodeX - ( ( -1 ) * jointNodeQ * sqrt(2) - bodyWidth / 2 * cos(135 deg) + ( ( 1 ) * nodeHalfWidth ) * sin(135 deg) ) ) ) + ( -1 ) * ( ( 1 ) * nodeHalfWidth ))"
equation "d450 = -memberWidth / 2"
equation "d451 = -( wall + 0.2 mm )"
equation "d454 = apertureRadius"
equation "d457 = bodyWidth / 2"
equation "d459 = abs(( -1 ) * ( ( ( -1 ) * jointNodeQ * sqrt(2) - bodyWidth / 2 * cos(180 deg) + ( ( -1 ) * nodeHalfWidth ) * sin(180 deg) ) + ( 0 ) * ( ( -1 ) * endNodeX - ( ( -1 ) * jointNodeQ * sqrt(2) - bodyWidth / 2 * cos(180 deg) + ( ( -1 ) * nodeHalfWidth ) * sin(180 deg) ) ) ) + ( 0 ) * ( ( -1 ) * nodeHalfWidth ))"
equation "d460 = abs(( 0 ) * ( ( ( -1 ) * jointNodeQ * sqrt(2) - bodyWidth / 2 * cos(180 deg) + ( ( -1 ) * nodeHalfWidth ) * sin(180 deg) ) + ( 0 ) * ( ( -1 ) * endNodeX - ( ( -1 ) * jointNodeQ * sqrt(2) - bodyWidth / 2 * cos(180 deg) + ( ( -1 ) * nodeHalfWidth ) * sin(180 deg) ) ) ) + ( 1 ) * ( ( -1 ) * nodeHalfWidth ))"
equation "d461 = abs(( -1 ) * ( ( ( -1 ) * jointNodeQ * sqrt(2) - bodyWidth / 2 * cos(180 deg) + ( ( 1 ) * nodeHalfWidth ) * sin(180 deg) ) + ( 0 ) * ( ( -1 ) * endNodeX - ( ( -1 ) * jointNodeQ * sqrt(2) - bodyWidth / 2 * cos(180 deg) + ( ( 1 ) * nodeHalfWidth ) * sin(180 deg) ) ) ) + ( 0 ) * ( ( 1 ) * nodeHalfWidth ))"
equation "d462 = abs(( 0 ) * ( ( ( -1 ) * jointNodeQ * sqrt(2) - bodyWidth / 2 * cos(180 deg) + ( ( 1 ) * nodeHalfWidth ) * sin(180 deg) ) + ( 0 ) * ( ( -1 ) * endNodeX - ( ( -1 ) * jointNodeQ * sqrt(2) - bodyWidth / 2 * cos(180 deg) + ( ( 1 ) * nodeHalfWidth ) * sin(180 deg) ) ) ) + ( 1 ) * ( ( 1 ) * nodeHalfWidth ))"
equation "d463 = abs(( -1 ) * ( ( ( -1 ) * jointNodeQ * sqrt(2) - bodyWidth / 2 * cos(180 deg) + ( ( -1 ) * nodeHalfWidth ) * sin(180 deg) ) + ( 0.333333333333333 ) * ( ( -1 ) * endNodeX - ( ( -1 ) * jointNodeQ * sqrt(2) - bodyWidth / 2 * cos(180 deg) + ( ( -1 ) * nodeHalfWidth ) * sin(180 deg) ) ) ) + ( 0 ) * ( ( -1 ) * nodeHalfWidth ))"
equation "d464 = abs(( 0 ) * ( ( ( -1 ) * jointNodeQ * sqrt(2) - bodyWidth / 2 * cos(180 deg) + ( ( -1 ) * nodeHalfWidth ) * sin(180 deg) ) + ( 0.333333333333333 ) * ( ( -1 ) * endNodeX - ( ( -1 ) * jointNodeQ * sqrt(2) - bodyWidth / 2 * cos(180 deg) + ( ( -1 ) * nodeHalfWidth ) * sin(180 deg) ) ) ) + ( 1 ) * ( ( -1 ) * nodeHalfWidth ))"
equation "d465 = memberWidth / 2"
equation "d466 = -( wall + 0.2 mm )"
equation "d468 = abs(( -1 ) * ( ( ( -1 ) * jointNodeQ * sqrt(2) - bodyWidth / 2 * cos(180 deg) + ( ( 1 ) * nodeHalfWidth ) * sin(180 deg) ) + ( 0 ) * ( ( -1 ) * endNodeX - ( ( -1 ) * jointNodeQ * sqrt(2) - bodyWidth / 2 * cos(180 deg) + ( ( 1 ) * nodeHalfWidth ) * sin(180 deg) ) ) ) + ( 0 ) * ( ( 1 ) * nodeHalfWidth ))"
equation "d469 = abs(( 0 ) * ( ( ( -1 ) * jointNodeQ * sqrt(2) - bodyWidth / 2 * cos(180 deg) + ( ( 1 ) * nodeHalfWidth ) * sin(180 deg) ) + ( 0 ) * ( ( -1 ) * endNodeX - ( ( -1 ) * jointNodeQ * sqrt(2) - bodyWidth / 2 * cos(180 deg) + ( ( 1 ) * nodeHalfWidth ) * sin(180 deg) ) ) ) + ( 1 ) * ( ( 1 ) * nodeHalfWidth ))"
equation "d470 = abs(( -1 ) * ( ( ( -1 ) * jointNodeQ * sqrt(2) - bodyWidth / 2 * cos(180 deg) + ( ( -1 ) * nodeHalfWidth ) * sin(180 deg) ) + ( 0.333333333333333 ) * ( ( -1 ) * endNodeX - ( ( -1 ) * jointNodeQ * sqrt(2) - bodyWidth / 2 * cos(180 deg) + ( ( -1 ) * nodeHalfWidth ) * sin(180 deg) ) ) ) + ( 0 ) * ( ( -1 ) * nodeHalfWidth ))"
equation "d471 = abs(( 0 ) * ( ( ( -1 ) * jointNodeQ * sqrt(2) - bodyWidth / 2 * cos(180 deg) + ( ( -1 ) * nodeHalfWidth ) * sin(180 deg) ) + ( 0.333333333333333 ) * ( ( -1 ) * endNodeX - ( ( -1 ) * jointNodeQ * sqrt(2) - bodyWidth / 2 * cos(180 deg) + ( ( -1 ) * nodeHalfWidth ) * sin(180 deg) ) ) ) + ( 1 ) * ( ( -1 ) * nodeHalfWidth ))"
equation "d472 = abs(( -1 ) * ( ( ( -1 ) * jointNodeQ * sqrt(2) - bodyWidth / 2 * cos(180 deg) + ( ( 1 ) * nodeHalfWidth ) * sin(180 deg) ) + ( 0.666666666666667 ) * ( ( -1 ) * endNodeX - ( ( -1 ) * jointNodeQ * sqrt(2) - bodyWidth / 2 * cos(180 deg) + ( ( 1 ) * nodeHalfWidth ) * sin(180 deg) ) ) ) + ( 0 ) * ( ( 1 ) * nodeHalfWidth ))"
equation "d473 = abs(( 0 ) * ( ( ( -1 ) * jointNodeQ * sqrt(2) - bodyWidth / 2 * cos(180 deg) + ( ( 1 ) * nodeHalfWidth ) * sin(180 deg) ) + ( 0.666666666666667 ) * ( ( -1 ) * endNodeX - ( ( -1 ) * jointNodeQ * sqrt(2) - bodyWidth / 2 * cos(180 deg) + ( ( 1 ) * nodeHalfWidth ) * sin(180 deg) ) ) ) + ( 1 ) * ( ( 1 ) * nodeHalfWidth ))"
equation "d474 = -memberWidth / 2"
equation "d475 = -( wall + 0.2 mm )"
equation "d477 = abs(( -1 ) * ( ( ( -1 ) * jointNodeQ * sqrt(2) - bodyWidth / 2 * cos(180 deg) + ( ( -1 ) * nodeHalfWidth ) * sin(180 deg) ) + ( 0.333333333333333 ) * ( ( -1 ) * endNodeX - ( ( -1 ) * jointNodeQ * sqrt(2) - bodyWidth / 2 * cos(180 deg) + ( ( -1 ) * nodeHalfWidth ) * sin(180 deg) ) ) ) + ( 0 ) * ( ( -1 ) * nodeHalfWidth ))"
equation "d478 = abs(( 0 ) * ( ( ( -1 ) * jointNodeQ * sqrt(2) - bodyWidth / 2 * cos(180 deg) + ( ( -1 ) * nodeHalfWidth ) * sin(180 deg) ) + ( 0.333333333333333 ) * ( ( -1 ) * endNodeX - ( ( -1 ) * jointNodeQ * sqrt(2) - bodyWidth / 2 * cos(180 deg) + ( ( -1 ) * nodeHalfWidth ) * sin(180 deg) ) ) ) + ( 1 ) * ( ( -1 ) * nodeHalfWidth ))"
equation "d479 = abs(( -1 ) * ( ( ( -1 ) * jointNodeQ * sqrt(2) - bodyWidth / 2 * cos(180 deg) + ( ( 1 ) * nodeHalfWidth ) * sin(180 deg) ) + ( 0.666666666666667 ) * ( ( -1 ) * endNodeX - ( ( -1 ) * jointNodeQ * sqrt(2) - bodyWidth / 2 * cos(180 deg) + ( ( 1 ) * nodeHalfWidth ) * sin(180 deg) ) ) ) + ( 0 ) * ( ( 1 ) * nodeHalfWidth ))"
equation "d480 = abs(( 0 ) * ( ( ( -1 ) * jointNodeQ * sqrt(2) - bodyWidth / 2 * cos(180 deg) + ( ( 1 ) * nodeHalfWidth ) * sin(180 deg) ) + ( 0.666666666666667 ) * ( ( -1 ) * endNodeX - ( ( -1 ) * jointNodeQ * sqrt(2) - bodyWidth / 2 * cos(180 deg) + ( ( 1 ) * nodeHalfWidth ) * sin(180 deg) ) ) ) + ( 1 ) * ( ( 1 ) * nodeHalfWidth ))"
equation "d481 = abs(( -1 ) * ( ( ( -1 ) * jointNodeQ * sqrt(2) - bodyWidth / 2 * cos(180 deg) + ( ( -1 ) * nodeHalfWidth ) * sin(180 deg) ) + ( 1 ) * ( ( -1 ) * endNodeX - ( ( -1 ) * jointNodeQ * sqrt(2) - bodyWidth / 2 * cos(180 deg) + ( ( -1 ) * nodeHalfWidth ) * sin(180 deg) ) ) ) + ( 0 ) * ( ( -1 ) * nodeHalfWidth ))"
equation "d482 = abs(( 0 ) * ( ( ( -1 ) * jointNodeQ * sqrt(2) - bodyWidth / 2 * cos(180 deg) + ( ( -1 ) * nodeHalfWidth ) * sin(180 deg) ) + ( 1 ) * ( ( -1 ) * endNodeX - ( ( -1 ) * jointNodeQ * sqrt(2) - bodyWidth / 2 * cos(180 deg) + ( ( -1 ) * nodeHalfWidth ) * sin(180 deg) ) ) ) + ( 1 ) * ( ( -1 ) * nodeHalfWidth ))"
equation "d483 = memberWidth / 2"
equation "d484 = -( wall + 0.2 mm )"
equation "d486 = abs(( -1 ) * ( ( ( -1 ) * jointNodeQ * sqrt(2) - bodyWidth / 2 * cos(180 deg) + ( ( 1 ) * nodeHalfWidth ) * sin(180 deg) ) + ( 0.666666666666667 ) * ( ( -1 ) * endNodeX - ( ( -1 ) * jointNodeQ * sqrt(2) - bodyWidth / 2 * cos(180 deg) + ( ( 1 ) * nodeHalfWidth ) * sin(180 deg) ) ) ) + ( 0 ) * ( ( 1 ) * nodeHalfWidth ))"
equation "d487 = abs(( 0 ) * ( ( ( -1 ) * jointNodeQ * sqrt(2) - bodyWidth / 2 * cos(180 deg) + ( ( 1 ) * nodeHalfWidth ) * sin(180 deg) ) + ( 0.666666666666667 ) * ( ( -1 ) * endNodeX - ( ( -1 ) * jointNodeQ * sqrt(2) - bodyWidth / 2 * cos(180 deg) + ( ( 1 ) * nodeHalfWidth ) * sin(180 deg) ) ) ) + ( 1 ) * ( ( 1 ) * nodeHalfWidth ))"
equation "d488 = abs(( -1 ) * ( ( ( -1 ) * jointNodeQ * sqrt(2) - bodyWidth / 2 * cos(180 deg) + ( ( -1 ) * nodeHalfWidth ) * sin(180 deg) ) + ( 1 ) * ( ( -1 ) * endNodeX - ( ( -1 ) * jointNodeQ * sqrt(2) - bodyWidth / 2 * cos(180 deg) + ( ( -1 ) * nodeHalfWidth ) * sin(180 deg) ) ) ) + ( 0 ) * ( ( -1 ) * nodeHalfWidth ))"
equation "d489 = abs(( 0 ) * ( ( ( -1 ) * jointNodeQ * sqrt(2) - bodyWidth / 2 * cos(180 deg) + ( ( -1 ) * nodeHalfWidth ) * sin(180 deg) ) + ( 1 ) * ( ( -1 ) * endNodeX - ( ( -1 ) * jointNodeQ * sqrt(2) - bodyWidth / 2 * cos(180 deg) + ( ( -1 ) * nodeHalfWidth ) * sin(180 deg) ) ) ) + ( 1 ) * ( ( -1 ) * nodeHalfWidth ))"
equation "d490 = abs(( -1 ) * ( ( ( -1 ) * jointNodeQ * sqrt(2) - bodyWidth / 2 * cos(180 deg) + ( ( 1 ) * nodeHalfWidth ) * sin(180 deg) ) + ( 1 ) * ( ( -1 ) * endNodeX - ( ( -1 ) * jointNodeQ * sqrt(2) - bodyWidth / 2 * cos(180 deg) + ( ( 1 ) * nodeHalfWidth ) * sin(180 deg) ) ) ) + ( 0 ) * ( ( 1 ) * nodeHalfWidth ))"
equation "d491 = abs(( 0 ) * ( ( ( -1 ) * jointNodeQ * sqrt(2) - bodyWidth / 2 * cos(180 deg) + ( ( 1 ) * nodeHalfWidth ) * sin(180 deg) ) + ( 1 ) * ( ( -1 ) * endNodeX - ( ( -1 ) * jointNodeQ * sqrt(2) - bodyWidth / 2 * cos(180 deg) + ( ( 1 ) * nodeHalfWidth ) * sin(180 deg) ) ) ) + ( 1 ) * ( ( 1 ) * nodeHalfWidth ))"
equation "d492 = -memberWidth / 2"
equation "d493 = -( wall + 0.2 mm )"
equation "d496 = apertureRadius"
equation "d499 = bodyWidth / 2"
equation "d501 = abs(( 1 ) * ( ( ( -1 ) * jointNodeQ * sqrt(2) - bodyWidth / 2 * cos(225 deg) + ( ( -1 ) * nodeHalfWidth ) * sin(225 deg) ) + ( 0 ) * ( ( -1 ) * endNodeX - ( ( -1 ) * jointNodeQ * sqrt(2) - bodyWidth / 2 * cos(225 deg) + ( ( -1 ) * nodeHalfWidth ) * sin(225 deg) ) ) ) + ( 0 ) * ( ( -1 ) * nodeHalfWidth ))"
equation "d502 = abs(( 0 ) * ( ( ( -1 ) * jointNodeQ * sqrt(2) - bodyWidth / 2 * cos(225 deg) + ( ( -1 ) * nodeHalfWidth ) * sin(225 deg) ) + ( 0 ) * ( ( -1 ) * endNodeX - ( ( -1 ) * jointNodeQ * sqrt(2) - bodyWidth / 2 * cos(225 deg) + ( ( -1 ) * nodeHalfWidth ) * sin(225 deg) ) ) ) + ( -1 ) * ( ( -1 ) * nodeHalfWidth ))"